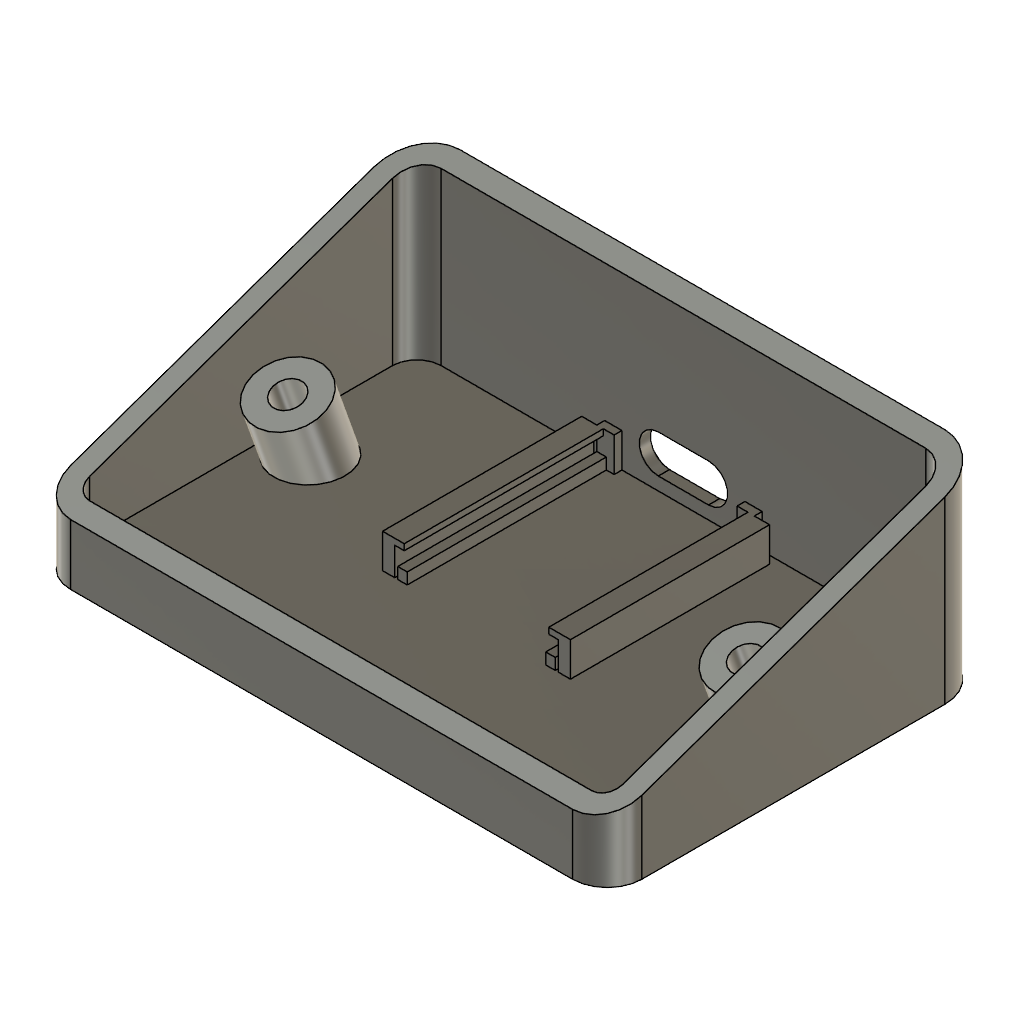
Case (Autodesk Fusion 360 design; units mm, degrees)
part number: 2026-10-25-18-44-29-577
Autodesk Fusion 360 part; units mm, degrees
sketch "01 Base footprint" plane through (0, 0, 0) normal (0, 0, 1) x (1, 0, 0)
  arc A0 (-33, -18) -> (-29, -22) centre (-29, -18) ccw
  arc A1 (29, -22) -> (33, -18) centre (29, -18) ccw
  arc A2 (33, 17) -> (28, 22) centre (28, 17) ccw
  arc A3 (-28, 22) -> (-33, 17) centre (-28, 17) ccw
  line L0 (-29, -22) -> (29, -22)
  line L1 (33, -18) -> (33, 17)
  line L2 (28, 22) -> (-28, 22)
  line L3 (-33, 17) -> (-33, -18)
  dimension "d64" = 29
  dimension "d65" = 18
  dimension "d66" = 4
  dimension "d67" = 29
  dimension "d68" = 18
  dimension "d69" = 4
  dimension "d70" = 28
  dimension "d71" = 17
  dimension "d72" = 5
  dimension "d73" = 28
  dimension "d74" = 17
  dimension "d75" = 5
  constraint horizontal A0.centre A0.start
  constraint vertical A0.centre A0.end
  constraint vertical A1.centre A1.start
  constraint horizontal A1.centre A1.end
  constraint horizontal A2.centre A2.start
  constraint vertical A2.centre A2.end
  constraint vertical A3.centre A3.start
  constraint horizontal A3.centre A3.end
  measures "d64" horizontal distance of origin A0.centre
  measures "d65" vertical distance of origin A0.centre
  measures "d66" radius of A0
  measures "d67" horizontal distance of origin A1.centre
  measures "d68" vertical distance of origin A1.centre
  measures "d69" radius of A1
  measures "d70" horizontal distance of origin A2.centre
  measures "d71" vertical distance of origin A2.centre
  measures "d72" radius of A2
  measures "d73" horizontal distance of origin A3.centre
  measures "d74" vertical distance of origin A3.centre
  measures "d75" radius of A3
extrude "01 Full height outer blank" add sketch "01 Base footprint" along normal blind 22.6
ref_plane "WorkPlane1" through (0, 0, 14.75) normal (0, 0, 1) x (1, 0, 0)
sketch "Reference axis for lid inclination" plane through (0, 0, 14.75) normal (0, 0, 1) x (1, 0, 0)
  line L0 (-40, 0) -> (40, 0) construction
ref_plane "WorkPlane2" through (0, 0, 14.75) normal (0, -0.332259, 0.943188) x (1, 0, 0)
sketch "02 Sloping rim trim" plane through (0, -4.6224, 13.1217) normal (0, -0.332259, 0.943188) x (1, 0, 0)
  line L0 (-50, -50) -> (50, -50)
  line L1 (50, -50) -> (50, 50)
  line L2 (50, 50) -> (-50, 50)
  line L3 (-50, 50) -> (-50, -50)
  dimension "d82" = 50
  dimension "d83" = 50
  dimension "d84" = 100
  dimension "d85" = 100
  measures "d82" horizontal distance of origin L0.start
  measures "d83" vertical distance of origin L0.start
  measures "d84" distance of L0.start L0.end
  measures "d85" distance of L0.end L1.end
extrude "02 Sloping upper rim" cut sketch "02 Sloping rim trim" along normal blind 50
ref_plane "WorkPlane3" through (0, 0, 2) normal (0, 0, 1) x (1, 0, 0)
sketch "03 Interior cavity" plane through (0, 0, 2) normal (0, 0, 1) x (1, 0, 0)
  arc A0 (-30.8, -18) -> (-29, -19.8) centre (-29, -18) ccw
  arc A1 (29, -19.8) -> (30.8, -18) centre (29, -18) ccw
  arc A2 (30.8, 17) -> (28, 19.8) centre (28, 17) ccw
  arc A3 (-28, 19.8) -> (-30.8, 17) centre (-28, 17) ccw
  line L0 (-29, -19.8) -> (29, -19.8)
  line L1 (30.8, -18) -> (30.8, 17)
  line L2 (28, 19.8) -> (-28, 19.8)
  line L3 (-30.8, 17) -> (-30.8, -18)
  dimension "d90" = 29
  dimension "d91" = 18
  dimension "d92" = 1.8
  dimension "d93" = 29
  dimension "d94" = 18
  dimension "d95" = 1.8
  dimension "d96" = 28
  dimension "d97" = 17
  dimension "d98" = 2.8
  dimension "d99" = 28
  dimension "d100" = 17
  dimension "d101" = 2.8
  constraint horizontal A0.centre A0.start
  constraint vertical A0.centre A0.end
  constraint vertical A1.centre A1.start
  constraint horizontal A1.centre A1.end
  constraint horizontal A2.centre A2.start
  constraint vertical A2.centre A2.end
  constraint vertical A3.centre A3.start
  constraint horizontal A3.centre A3.end
  measures "d90" horizontal distance of origin A0.centre
  measures "d91" vertical distance of origin A0.centre
  measures "d92" radius of A0
  measures "d93" horizontal distance of origin A1.centre
  measures "d94" vertical distance of origin A1.centre
  measures "d95" radius of A1
  measures "d96" horizontal distance of origin A2.centre
  measures "d97" vertical distance of origin A2.centre
  measures "d98" radius of A2
  measures "d99" horizontal distance of origin A3.centre
  measures "d100" vertical distance of origin A3.centre
  measures "d101" radius of A3
extrude "03 Hollow shell - floor 2 mm" cut sketch "03 Interior cavity" along normal blind 23.5
ref_plane "WorkPlane4" through (0, 1.7277, 9.8454) normal (0, -0.332259, 0.943188) x (1, 0, 0)
sketch "04 Inclined lower screw columns" plane through (0, -2.8947, 8.2171) normal (0, -0.332259, 0.943188) x (1, 0, 0)
  circle A0 centre (-26.5, 3.7008) radius 4
  circle A1 centre (26.5, 3.7008) radius 4
  dimension "d106" = 26.5
  dimension "d107" = 3.7008
  dimension "d108" = 8
  dimension "d109" = 26.5
  dimension "d110" = 3.7008
  dimension "d111" = 8
  measures "d106" horizontal distance of origin A0.centre
  measures "d107" vertical distance of origin A0.centre
  measures "d108" diameter of A0
  measures "d109" horizontal distance of origin A1.centre
  measures "d110" vertical distance of origin A1.centre
  measures "d111" diameter of A1
extrude "04 Inclined lower screw columns (1)" add sketch "04 Inclined lower screw columns" against normal blind 13.55
sketch "05 Trim columns flush to desk" plane through (0, 0, 0) normal (0, 0, 1) x (1, 0, 0)
  line L0 (-50, -50) -> (50, -50)
  line L1 (50, -50) -> (50, 50)
  line L2 (50, 50) -> (-50, 50)
  line L3 (-50, 50) -> (-50, -50)
  dimension "d114" = 50
  dimension "d115" = 50
  dimension "d116" = 100
  dimension "d117" = 100
  measures "d114" horizontal distance of origin L0.start
  measures "d115" vertical distance of origin L0.start
  measures "d116" distance of L0.start L0.end
  measures "d117" distance of L0.end L1.end
extrude "05 Flat underside" cut sketch "05 Trim columns flush to desk" against normal blind 20
ref_plane "WorkPlane5" through (0, 0, 2) normal (0, 0, 1) x (1, 0, 0)
sketch "06 PCB guide rails" plane through (0, 0, 2) normal (0, 0, 1) x (1, 0, 0)
  line L0 (-10.85, -4.1) -> (-9.45, -4.1)
  line L1 (-9.45, -4.1) -> (-9.45, 18.9)
  line L2 (-9.45, 18.9) -> (-10.85, 18.9)
  line L3 (-10.85, 18.9) -> (-10.85, -4.1)
  line L4 (9.45, -4.1) -> (10.85, -4.1)
  line L5 (10.85, -4.1) -> (10.85, 18.9)
  line L6 (10.85, 18.9) -> (9.45, 18.9)
  line L7 (9.45, 18.9) -> (9.45, -4.1)
  dimension "d122" = 10.85
  dimension "d123" = 4.1
  dimension "d124" = 1.4
  dimension "d125" = 23
  dimension "d126" = 9.45
  dimension "d127" = 4.1
  dimension "d128" = 1.4
  dimension "d129" = 23
  measures "d122" horizontal distance of origin L0.start
  measures "d123" vertical distance of origin L0.start
  measures "d124" distance of L0.start L0.end
  measures "d125" distance of L0.end L1.end
  measures "d126" horizontal distance of origin L4.start
  measures "d127" vertical distance of origin L4.start
  measures "d128" distance of L4.start L4.end
  measures "d129" distance of L4.end L5.end
extrude "06 PCB guide rails (1)" add sketch "06 PCB guide rails" along normal blind 3.95
ref_plane "WorkPlane6" through (0, 0, 2) normal (0, 0, 1) x (1, 0, 0)
sketch "07 PCB support ledges" plane through (0, 0, 2) normal (0, 0, 1) x (1, 0, 0)
  line L0 (-9.1, -4.1) -> (-8, -4.1)
  line L1 (-8, -4.1) -> (-8, 18.9)
  line L2 (-8, 18.9) -> (-9.1, 18.9)
  line L3 (-9.1, 18.9) -> (-9.1, -4.1)
  line L4 (8, -4.1) -> (9.1, -4.1)
  line L5 (9.1, -4.1) -> (9.1, 18.9)
  line L6 (9.1, 18.9) -> (8, 18.9)
  line L7 (8, 18.9) -> (8, -4.1)
  dimension "d134" = 9.1
  dimension "d135" = 4.1
  dimension "d136" = 1.1
  dimension "d137" = 23
  dimension "d138" = 8
  dimension "d139" = 4.1
  dimension "d140" = 1.1
  dimension "d141" = 23
  measures "d134" horizontal distance of origin L0.start
  measures "d135" vertical distance of origin L0.start
  measures "d136" distance of L0.start L0.end
  measures "d137" distance of L0.end L1.end
  measures "d138" horizontal distance of origin L4.start
  measures "d139" vertical distance of origin L4.start
  measures "d140" distance of L4.start L4.end
  measures "d141" distance of L4.end L5.end
extrude "07 PCB support ledges (1)" add sketch "07 PCB support ledges" along normal blind 1.3
ref_plane "WorkPlane7" through (0, 0, 5.25) normal (0, 0, 1) x (1, 0, 0)
sketch "08 PCB retaining lips" plane through (0, 0, 5.25) normal (0, 0, 1) x (1, 0, 0)
  line L0 (-9.45, -4.1) -> (-8.35, -4.1)
  line L1 (-8.35, -4.1) -> (-8.35, 18.9)
  line L2 (-8.35, 18.9) -> (-9.45, 18.9)
  line L3 (-9.45, 18.9) -> (-9.45, -4.1)
  line L4 (8.35, -4.1) -> (9.45, -4.1)
  line L5 (9.45, -4.1) -> (9.45, 18.9)
  line L6 (9.45, 18.9) -> (8.35, 18.9)
  line L7 (8.35, 18.9) -> (8.35, -4.1)
  dimension "d146" = 9.45
  dimension "d147" = 4.1
  dimension "d148" = 1.1
  dimension "d149" = 23
  dimension "d150" = 8.35
  dimension "d151" = 4.1
  dimension "d152" = 1.1
  dimension "d153" = 23
  measures "d146" horizontal distance of origin L0.start
  measures "d147" vertical distance of origin L0.start
  measures "d148" distance of L0.start L0.end
  measures "d149" distance of L0.end L1.end
  measures "d150" horizontal distance of origin L4.start
  measures "d151" vertical distance of origin L4.start
  measures "d152" distance of L4.start L4.end
  measures "d153" distance of L4.end L5.end
extrude "08 PCB retaining lips (1)" add sketch "08 PCB retaining lips" along normal blind 0.7
ref_plane "WorkPlane8" through (0, 0, 2) normal (0, 0, 1) x (1, 0, 0)
sketch "09 Rear corner stops - USB channel clear" plane through (0, 0, 2) normal (0, 0, 1) x (1, 0, 0)
  line L0 (-9.1, 18.9) -> (-7.1, 18.9)
  line L1 (-7.1, 18.9) -> (-7.1, 20)
  line L2 (-7.1, 20) -> (-9.1, 20)
  line L3 (-9.1, 20) -> (-9.1, 18.9)
  line L4 (7.1, 18.9) -> (9.1, 18.9)
  line L5 (9.1, 18.9) -> (9.1, 20)
  line L6 (9.1, 20) -> (7.1, 20)
  line L7 (7.1, 20) -> (7.1, 18.9)
  dimension "d158" = 9.1
  dimension "d159" = 18.9
  dimension "d160" = 2
  dimension "d161" = 1.1
  dimension "d162" = 7.1
  dimension "d163" = 18.9
  dimension "d164" = 2
  dimension "d165" = 1.1
  measures "d158" horizontal distance of origin L0.start
  measures "d159" vertical distance of origin L0.start
  measures "d160" distance of L0.start L0.end
  measures "d161" distance of L0.end L1.end
  measures "d162" horizontal distance of origin L4.start
  measures "d163" vertical distance of origin L4.start
  measures "d164" distance of L4.start L4.end
  measures "d165" distance of L4.end L5.end
extrude "09 Rear corner stops - USB channel clear (1)" add sketch "09 Rear corner stops - USB channel clear" along normal blind 3.95
ref_plane "WorkPlane9" through (0, 6.5621, -3.878) normal (0, -0.332259, 0.943188) x (1, 0, 0)
sketch "10 Angled M3 clearance" plane through (0, 1.9397, -5.5063) normal (0, -0.332259, 0.943188) x (1, 0, 0)
  circle A0 centre (-26.5, 3.7008) radius 1.7
  circle A1 centre (26.5, 3.7008) radius 1.7
  dimension "d170" = 26.5
  dimension "d171" = 3.7008
  dimension "d172" = 3.4
  dimension "d173" = 26.5
  dimension "d174" = 3.7008
  dimension "d175" = 3.4
  measures "d170" horizontal distance of origin A0.centre
  measures "d171" vertical distance of origin A0.centre
  measures "d172" diameter of A0
  measures "d173" horizontal distance of origin A1.centre
  measures "d174" vertical distance of origin A1.centre
  measures "d175" diameter of A1
extrude "10 Angled M3 clearance (1)" cut sketch "10 Angled M3 clearance" along normal blind 24.75
ref_plane "WorkPlane10" through (0, 6.5621, -3.878) normal (0, -0.332259, 0.943188) x (1, 0, 0)
sketch "11 Screw head recesses" plane through (0, 1.9397, -5.5063) normal (0, -0.332259, 0.943188) x (1, 0, 0)
  circle A0 centre (-26.5, 3.7008) radius 3.2
  circle A1 centre (26.5, 3.7008) radius 3.2
  dimension "d180" = 26.5
  dimension "d181" = 3.7008
  dimension "d182" = 6.4
  dimension "d183" = 26.5
  dimension "d184" = 3.7008
  dimension "d185" = 6.4
  measures "d180" horizontal distance of origin A0.centre
  measures "d181" vertical distance of origin A0.centre
  measures "d182" diameter of A0
  measures "d183" horizontal distance of origin A1.centre
  measures "d184" vertical distance of origin A1.centre
  measures "d185" diameter of A1
extrude "11 Screw head recesses (1)" cut sketch "11 Screw head recesses" along normal blind 7
ref_plane "WorkPlane11" through (0, 22.25, 0) normal (0, 1, 0) x (0, 0, 1)
sketch "12 USB-C capsule passage" plane through (0, 22.25, 0) normal (0, 1, 0) x (1, 0, 0)
  arc A0 (2.9, -7.9) -> (2.9, -3.5) centre (2.9, -5.7) ccw
  arc A1 (-2.9, -3.5) -> (-2.9, -7.9) centre (-2.9, -5.7) ccw
  line L0 (2.9, -3.5) -> (-2.9, -3.5)
  line L1 (-2.9, -7.9) -> (2.9, -7.9)
  dimension "d190" = 2.9
  dimension "d192" = 2.2
  dimension "d193" = 2.9
  dimension "d194" = 5.7
  dimension "d195" = 2.2
  constraint vertical A0.centre A0.start
  constraint vertical A0.centre A0.end
  constraint vertical A1.centre A1.start
  constraint vertical A1.centre A1.end
  measures "d190" horizontal distance of origin A0.centre
  measures "d192" radius of A0
  measures "d193" horizontal distance of origin A1.centre
  measures "d194" vertical distance of origin A1.centre
  measures "d195" radius of A1
extrude "12 USB-C capsule passage (1)" cut sketch "12 USB-C capsule passage" against normal blind 2.9
sketch "13 USB plug relief" plane through (0, 22.25, 0) normal (0, 1, 0) x (1, 0, 0)
  arc A0 (3.1, -9) -> (3.1, -2.4) centre (3.1, -5.7) ccw
  arc A1 (-3.1, -2.4) -> (-3.1, -9) centre (-3.1, -5.7) ccw
  line L0 (3.1, -2.4) -> (-3.1, -2.4)
  line L1 (-3.1, -9) -> (3.1, -9)
  dimension "d198" = 3.1
  dimension "d200" = 3.3
  dimension "d201" = 3.1
  dimension "d202" = 5.7
  dimension "d203" = 3.3
  constraint vertical A0.centre A0.start
  constraint vertical A0.centre A0.end
  constraint vertical A1.centre A1.start
  constraint vertical A1.centre A1.end
  measures "d198" horizontal distance of origin A0.centre
  measures "d200" radius of A0
  measures "d201" horizontal distance of origin A1.centre
  measures "d202" vertical distance of origin A1.centre
  measures "d203" radius of A1
extrude "13 USB plug relief (1)" cut sketch "13 USB plug relief" against normal blind 1.15
equation "case_w = 66 mm" comment "OpenSCAD V6.15 source"
equation "case_d = 44 mm" comment "OpenSCAD V6.15 source"
equation "bottom_h = 17 mm" comment "OpenSCAD V6.15 source"
equation "top_t = 3 mm" comment "OpenSCAD V6.15 source"
equation "wall = 2.2 mm" comment "OpenSCAD V6.15 source"
equation "front_corner_r = 4.0 mm" comment "OpenSCAD V6.15 source"
equation "rear_corner_r = 5.0 mm" comment "OpenSCAD V6.15 source"
equation "fit = 0.55 mm" comment "OpenSCAD V6.15 source"
equation "oled_pcb_w = 38 mm" comment "OpenSCAD V6.15 source"
equation "oled_pcb_d = 12 mm" comment "OpenSCAD V6.15 source"
equation "oled_pixel_w = 22.74 mm" comment "OpenSCAD V6.15 source"
equation "oled_pixel_d = 5.86 mm" comment "OpenSCAD V6.15 source"
equation "oled_pixel_offset_x = 0 mm" comment "OpenSCAD V6.15 source"
equation "oled_pixel_offset_y = 0 mm" comment "OpenSCAD V6.15 source"
equation "oled_center_x = -11 mm" comment "OpenSCAD V6.15 source"
equation "oled_center_y = 9 mm" comment "OpenSCAD V6.15 source"
equation "oled_recess_depth = 1.4 mm" comment "OpenSCAD V6.15 source"
equation "oled_pcb_clearance = 0.80 mm" comment "OpenSCAD V6.15 source"
equation "oled_skirt_channel_depth = 3.25 mm" comment "OpenSCAD V6.15 source"
equation "oled_bezel_w = 27.2 mm" comment "OpenSCAD V6.15 source"
equation "oled_bezel_d = 9.0 mm" comment "OpenSCAD V6.15 source"
equation "oled_bezel_depth = 1.2 mm" comment "OpenSCAD V6.15 source"
equation "mx_cutout = 14.10 mm" comment "OpenSCAD V6.15 source"
equation "mx_spacing = 19.05 mm" comment "OpenSCAD V6.15 source"
equation "mx_row_y = -10.5 mm" comment "OpenSCAD V6.15 source"
equation "mx_plate_thickness = 1.5 mm" comment "OpenSCAD V6.15 source"
equation "mx_recess_size = 16.0 mm" comment "OpenSCAD V6.15 source"
equation "encoder_x = mx_spacing" comment "OpenSCAD V6.15 source"
equation "encoder_y = 9 mm" comment "OpenSCAD V6.15 source"
equation "encoder_hole = 7.2 mm" comment "OpenSCAD V6.15 source"
equation "screw_clearance = 3.4 mm" comment "OpenSCAD V6.15 source"
equation "screw_head = 6.4 mm" comment "OpenSCAD V6.15 source"
equation "screw_head_depth = 2.0 mm" comment "OpenSCAD V6.15 source"
equation "pilot_hole = 2.7 mm" comment "OpenSCAD V6.15 source"
equation "boss_od = 6.5 mm" comment "OpenSCAD V6.15 source"
equation "boss_inset = 6.5 mm" comment "OpenSCAD V6.15 source"
equation "top_boss_depth = 5.0 mm" comment "OpenSCAD V6.15 source"
equation "boss_mating_clearance = 0.20 mm" comment "OpenSCAD V6.15 source"
equation "usb_w = 10.2 mm" comment "OpenSCAD V6.15 source"
equation "usb_h = 4.4 mm" comment "OpenSCAD V6.15 source"
equation "usb_bezel_w = 12.8 mm" comment "OpenSCAD V6.15 source"
equation "usb_bezel_h = 6.6 mm" comment "OpenSCAD V6.15 source"
equation "usb_bezel_depth = 0.9 mm" comment "OpenSCAD V6.15 source"
equation "usb_center_x = 0 mm" comment "OpenSCAD V6.15 source"
equation "usb_center_z = 5.7 mm" comment "OpenSCAD V6.15 source"
equation "mini_board_w = 18.2 mm" comment "OpenSCAD V6.15 source"
equation "mini_board_l = 23.0 mm" comment "OpenSCAD V6.15 source"
equation "mini_board_t = 1.6 mm" comment "OpenSCAD V6.15 source"
equation "mini_board_center_y = 7.4 mm" comment "OpenSCAD V6.15 source"
equation "mini_board_bottom_z = 3.3 mm" comment "OpenSCAD V6.15 source"
equation "mini_board_clearance = 0.35 mm" comment "OpenSCAD V6.15 source"
equation "mini_rail_t = 1.4 mm" comment "OpenSCAD V6.15 source"
equation "mini_lip_w = 1.1 mm" comment "OpenSCAD V6.15 source"
equation "front_wall_h = 7.0 mm" comment "OpenSCAD V6.15 source"
equation "rear_wall_h = 22.5 mm" comment "OpenSCAD V6.15 source"
equation "top_center_h = ( front_wall_h + rear_wall_h ) / 2" comment "OpenSCAD V6.15 source"
equation "tilt_angle = atan(( rear_wall_h - front_wall_h ) / case_d)" comment "OpenSCAD V6.15 source"
equation "lid_d = case_d / cos(tilt_angle)" comment "OpenSCAD V6.15 source"
equation "floor_t = 2 mm" comment "V6.15 construction dimension"
equation "skirt_depth = 3 mm" comment "V6.15 construction dimension"
equation "skirt_overlap = 0.2 mm" comment "V6.15 construction dimension"
equation "screw_y = -1.2 mm" comment "V6.15 construction dimension"
equation "rail_top = mini_board_bottom_z + mini_board_t + mini_board_clearance + 0.7 mm" comment "V6.15 construction dimension"
equation "d64 = -( ( 0 mm ) - ( ( case_w ) / 2 - ( front_corner_r ) ) )"
equation "d65 = -( ( 0 mm ) - ( ( case_d ) / 2 - ( front_corner_r ) ) )"
equation "d66 = front_corner_r"
equation "d67 = ( 0 mm ) + ( ( case_w ) / 2 - ( front_corner_r ) )"
equation "d69 = front_corner_r"
equation "d70 = ( 0 mm ) + ( ( case_w ) / 2 - ( rear_corner_r ) )"
equation "d71 = ( 0 mm ) + ( ( case_d ) / 2 - ( rear_corner_r ) )"
equation "d72 = rear_corner_r"
equation "d73 = -( ( 0 mm ) - ( ( case_w ) / 2 - ( rear_corner_r ) ) )"
equation "d74 = ( 0 mm ) + ( ( case_d ) / 2 - ( rear_corner_r ) )"
equation "d75 = rear_corner_r"
equation "d76 = rear_wall_h + 0.1 mm"
equation "d78 = top_center_h"
equation "d80 = tilt_angle"
equation "d82 = -( ( 0 mm ) - ( 100 mm ) / 2 )"
equation "d83 = -( ( 0 mm ) - ( 100 mm ) / 2 )"
equation "d88 = floor_t"
equation "d90 = -( ( 0 mm ) - ( ( case_w - 2 * wall ) / 2 - ( front_corner_r - wall ) ) )"
equation "d91 = -( ( 0 mm ) - ( ( case_d - 2 * wall ) / 2 - ( front_corner_r - wall ) ) )"
equation "d92 = front_corner_r - wall"
equation "d93 = ( 0 mm ) + ( ( case_w - 2 * wall ) / 2 - ( front_corner_r - wall ) )"
equation "d95 = front_corner_r - wall"
equation "d96 = ( 0 mm ) + ( ( case_w - 2 * wall ) / 2 - ( rear_corner_r - wall ) )"
equation "d97 = ( 0 mm ) + ( ( case_d - 2 * wall ) / 2 - ( rear_corner_r - wall ) )"
equation "d98 = rear_corner_r - wall"
equation "d99 = -( ( 0 mm ) - ( ( case_w - 2 * wall ) / 2 - ( rear_corner_r - wall ) ) )"
equation "d100 = ( 0 mm ) + ( ( case_d - 2 * wall ) / 2 - ( rear_corner_r - wall ) )"
equation "d101 = rear_corner_r - wall"
equation "d102 = rear_wall_h + 1 mm"
equation "d104 = -top_boss_depth - boss_mating_clearance"
equation "d106 = -( -26.5 mm )"
equation "d108 = boss_od + 1.5 mm"
equation "d111 = boss_od + 1.5 mm"
equation "d112 = -( top_center_h + 4 mm - top_boss_depth - boss_mating_clearance )"
equation "d114 = -( ( 0 mm ) - ( 100 mm ) / 2 )"
equation "d115 = -( ( 0 mm ) - ( 100 mm ) / 2 )"
equation "d118 = -( 20 mm )"
equation "d120 = floor_t"
equation "d122 = -( ( -( mini_board_w / 2 + mini_board_clearance + mini_rail_t / 2 ) ) - ( mini_rail_t ) / 2 )"
equation "d123 = -( ( mini_board_center_y ) - ( mini_board_l ) / 2 )"
equation "d124 = mini_rail_t"
equation "d125 = mini_board_l"
equation "d126 = ( ( mini_board_w / 2 + mini_board_clearance + mini_rail_t / 2 ) ) - ( mini_rail_t ) / 2"
equation "d128 = mini_rail_t"
equation "d129 = mini_board_l"
equation "d130 = rail_top - floor_t"
equation "d132 = floor_t"
equation "d134 = -( ( -( mini_board_w / 2 - 0.55 mm ) ) - ( 1.1 mm ) / 2 )"
equation "d135 = -( ( mini_board_center_y ) - ( mini_board_l ) / 2 )"
equation "d137 = mini_board_l"
equation "d138 = ( ( mini_board_w / 2 - 0.55 mm ) ) - ( 1.1 mm ) / 2"
equation "d141 = mini_board_l"
equation "d142 = mini_board_bottom_z - floor_t"
equation "d144 = rail_top - 0.7 mm"
equation "d146 = -( ( -( mini_board_w / 2 + mini_board_clearance - mini_lip_w / 2 ) ) - ( mini_lip_w ) / 2 )"
equation "d147 = -( ( mini_board_center_y ) - ( mini_board_l ) / 2 )"
equation "d148 = mini_lip_w"
equation "d149 = mini_board_l"
equation "d150 = ( ( mini_board_w / 2 + mini_board_clearance - mini_lip_w / 2 ) ) - ( mini_lip_w ) / 2"
equation "d152 = mini_lip_w"
equation "d153 = mini_board_l"
equation "d156 = floor_t"
equation "d158 = -( ( -( mini_board_w / 2 - 1 mm ) ) - ( 2 mm ) / 2 )"
equation "d159 = ( mini_board_center_y + mini_board_l / 2 + 0.55 mm ) - ( 1.1 mm ) / 2"
equation "d162 = ( ( mini_board_w / 2 - 1 mm ) ) - ( 2 mm ) / 2"
equation "d166 = rail_top - floor_t"
equation "d168 = -top_center_h - 5 mm"
equation "d170 = -( -26.5 mm )"
equation "d172 = screw_clearance"
equation "d175 = screw_clearance"
equation "d176 = top_center_h + 10 mm"
equation "d178 = -top_center_h - 5 mm"
equation "d180 = -( -26.5 mm )"
equation "d182 = screw_head"
equation "d185 = screw_head"
equation "d188 = case_d / 2 + 0.25 mm"
equation "d190 = ( usb_w - usb_h ) / 2"
equation "d191 = -( -usb_center_z )"
equation "d192 = usb_h / 2"
equation "d193 = -( -( usb_w - usb_h ) / 2 )"
equation "d195 = usb_h / 2"
equation "d196 = -( wall + 0.7 mm )"
equation "d198 = ( usb_bezel_w - usb_bezel_h ) / 2"
equation "d199 = -( -usb_center_z )"
equation "d200 = usb_bezel_h / 2"
equation "d201 = -( -( usb_bezel_w - usb_bezel_h ) / 2 )"
equation "d203 = usb_bezel_h / 2"
equation "d204 = -( usb_bezel_depth + 0.25 mm )"
named bodies: "Bottom V6.15"
